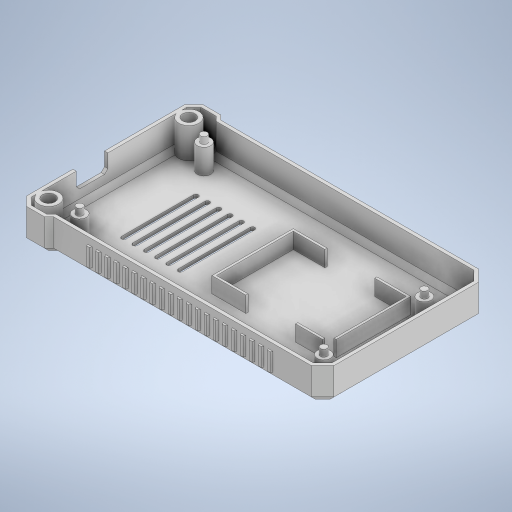
# Autodesk Inventor part: Coque V2
Saved by Autodesk Inventor 2024 (Build 280153000, 153)
## iProperties
Created: 2026-10-31
Part Number: Coque V2
Material: Générique
Document SubType Name: Modeling
Designer: berno
Density: 1 g/cm^3
Appearance: Par défaut
Author: berno
Autodesk Inventor part; units mm, degrees
sketch "Esq Coque" plane through (0, 0, 0) normal (0, 1, 0) x (-1, 0, 0)
  line L0 (-63, -32) -> (-63, 32)
  line L1 (-63, 32) -> (-58, 37)
  line L2 (-58, 37) -> (56, 37)
  line L3 (56, 37) -> (58, 39)
  line L4 (58, 39) -> (66, 39)
  line L5 (66, 39) -> (70, 35)
  line L6 (70, 35) -> (70, -35)
  line L7 (70, -35) -> (66, -39)
  line L8 (66, -39) -> (58, -39)
  line L9 (58, -39) -> (56, -37)
  line L10 (56, -37) -> (-58, -37)
  line L11 (-58, -37) -> (-63, -32)
  constraints: 24 end point
extrude "Coque" add sketch "Esq Coque" along normal blind 15
chamfer "Chanfrein dos" distance 3 angle 45 12 edges at (60.5, 0, 34.5) (1, 0, 37) (-57, 0, 38) (-62, 0, 39) (-68, 0, 37) (-70, 0, 0) (-68, 0, -37) (-62, 0, -39) (-57, 0, -38) (1, 0, -37) (60.5, 0, -34.5) (63, 0, 0)
shell "Evidement" thickness 1.5 removed faces 1 at (-18, 15, -12.3333)
ref_plane "Plan de construction1" through (0, 1.5, 0) normal (0, 1, 0) x (-1, 0, 0)
sketch "Esq Logement batterie" plane through (0, 1.5, 0) normal (0, 1, 0) x (-1, 0, 0)
  line L0 (5, -18) -> (4, -18)
  line L1 (4, -18) -> (4, 18)
  line L2 (4, 18) -> (5, 18)
  line L3 (5, 18) -> (5, -18)
  line L4 (4, 17) -> (-10, 17)
  line L5 (-10, 17) -> (-10, 18)
  line L6 (-10, 18) -> (4, 18)
  line L7 (4, 18) -> (4, 17)
  line L8 (4, -18) -> (-10, -18)
  line L9 (-10, -18) -> (-10, -17)
  line L10 (-10, -17) -> (4, -17)
  line L11 (4, -17) -> (4, -18)
  line L12 (-32, 17) -> (-44, 17)
  line L13 (-44, 17) -> (-44, 18)
  line L14 (-44, 18) -> (-32, 18)
  line L15 (-32, 18) -> (-32, 17)
  line L16 (-32, -18) -> (-46, -18)
  line L17 (-46, -18) -> (-46, -17)
  line L18 (-46, -17) -> (-32, -17)
  line L19 (-32, -17) -> (-32, -18)
  line L20 (-46, -18) -> (-47, -18)
  line L21 (-47, -18) -> (-47, 15)
  line L22 (-47, 15) -> (-46, 15)
  line L23 (-46, 15) -> (-46, -18)
  constraints: 48 end point, 12 parallel, 6 horizontal, 6 perpendicular
extrude "Logement batterie" add sketch "Esq Logement batterie" along normal blind 7
ref_plane "Plan de construction2" through (0, 1.5, 0) normal (0, 1, 0) x (-1, 0, 0)
sketch "Esq Plots carte" plane through (0, 1.5, 0) normal (0, 1, 0) x (-1, 0, 0)
  circle A0 centre (-54, -17) radius 3
  circle A1 centre (54, -27.5) radius 3
  circle A2 centre (54, 27.5) radius 3
  circle A3 centre (-54, 27.5) radius 3
  constraints: 4 centre point
extrude "Plots carte" add sketch "Esq Plots carte" along normal blind 11
ref_plane "Plan de construction3" through (0, 12.5, 0) normal (0, 1, 0) x (-1, 0, 0)
sketch "Esq Pions carte" plane through (0, 12.5, 0) normal (0, 1, 0) x (-1, 0, 0)
  circle A0 centre (-54, -17) radius 1.5
  circle A1 centre (54, -27.5) radius 1.5
  circle A2 centre (54, 27.5) radius 1.5
  circle A3 centre (-54, 27.5) radius 1.5
  constraints: 4 centre point
extrude "Pions carte" add sketch "Esq Pions carte" along normal blind 3
ref_plane "Plan de construction4" through (0, 1.5, 0) normal (0, 1, 0) x (-1, 0, 0)
sketch "Esq Plots inserts" plane through (0, 1.5, 0) normal (0, 1, 0) x (-1, 0, 0)
  circle A0 centre (64.2, 31) radius 4.5
  circle A1 centre (64.2, -31) radius 4.5
  constraints: 2 centre point
extrude "Plots inserts" add sketch "Esq Plots inserts" along normal blind 13.5
ref_plane "Plan de construction5" through (0, 15, 0) normal (0, 1, 0) x (-1, 0, 0)
sketch "Esq Trous inserts M4" plane through (0, 15, 0) normal (0, 1, 0) x (-1, 0, 0)
  circle A0 centre (64.2, 31) radius 2.8
  circle A1 centre (64.2, -31) radius 2.8
  constraints: 2 centre point
extrude "Trous inserts M4" cut sketch "Esq Trous inserts M4" against normal blind 8.5
ref_plane "Plan de construction6" through (-70, 0, 0) normal (1, 0, 0) x (0, 1, 0)
ref_plane "Plan de construction7" through (0, 0, 14.5) normal (0, 0, 1) x (1, 0, 0)
sketch "Esq Fente patte Z+" plane through (0, 0, 14.5) normal (0, 0, 1) x (1, 0, 0)
  line L0 (61, 12.2) -> (62.5, 12.2)
  line L1 (62.5, 12.2) -> (62.5, 13.7)
  line L2 (62.5, 13.7) -> (61.9, 13.7)
  line L3 (61.9, 13.7) -> (61.5, 14.1)
  line L4 (61.5, 14.1) -> (61, 14.1)
  line L5 (61, 14.1) -> (61, 12.2)
  constraints: 12 end point
extrude "Fente patte Z+" cut sketch "Esq Fente patte Z+" along normal mid plane 17
ref_plane "Plan de construction8" through (0, 0, -14.5) normal (0, 0, 1) x (1, 0, 0)
sketch "Esq Fente patte Z-" plane through (0, 0, -14.5) normal (0, 0, 1) x (1, 0, 0)
  line L0 (61, 12.2) -> (62.5, 12.2)
  line L1 (62.5, 12.2) -> (62.5, 13.7)
  line L2 (62.5, 13.7) -> (61.9, 13.7)
  line L3 (61.9, 13.7) -> (61.5, 14.1)
  line L4 (61.5, 14.1) -> (61, 14.1)
  line L5 (61, 14.1) -> (61, 12.2)
  constraints: 12 end point
extrude "Fente patte Z-" cut sketch "Esq Fente patte Z-" along normal mid plane 17
sketch "Esq Ventilation" plane through (0, 0, 0) normal (0, 1, 0) x (-1, 0, 0)
  line L0 (45, -16) -> (45, 16)
  line L1 (47, 16) -> (47, -16)
  arc A0 (47, 16) -> (45, 16) centre (46, 16) ccw
  arc A1 (45, -16) -> (47, -16) centre (46, -16) ccw
  line L2 (40, -16) -> (40, 16)
  line L3 (42, 16) -> (42, -16)
  arc A2 (42, 16) -> (40, 16) centre (41, 16) ccw
  arc A3 (40, -16) -> (42, -16) centre (41, -16) ccw
  line L4 (35, -16) -> (35, 16)
  line L5 (37, 16) -> (37, -16)
  arc A4 (37, 16) -> (35, 16) centre (36, 16) ccw
  arc A5 (35, -16) -> (37, -16) centre (36, -16) ccw
  line L6 (30, -16) -> (30, 16)
  line L7 (32, 16) -> (32, -16)
  arc A6 (32, 16) -> (30, 16) centre (31, 16) ccw
  arc A7 (30, -16) -> (32, -16) centre (31, -16) ccw
  line L8 (25, -16) -> (25, 16)
  line L9 (27, 16) -> (27, -16)
  arc A8 (27, 16) -> (25, 16) centre (26, 16) ccw
  arc A9 (25, -16) -> (27, -16) centre (26, -16) ccw
  line L10 (20, -16) -> (20, 16)
  line L11 (22, 16) -> (22, -16)
  arc A10 (22, 16) -> (20, 16) centre (21, 16) ccw
  arc A11 (20, -16) -> (22, -16) centre (21, -16) ccw
  constraints: 24 end point, 24 point on circle, 12 centre point
extrude "Ventilation" cut sketch "Esq Ventilation" along normal blind 2.5
ref_plane "Plan de construction9" through (-70, 0, 0) normal (1, 0, 0) x (0, 1, 0)
sketch "Esq Ouverture USB-C" plane through (-70, 0, 0) normal (1, 0, 0) x (0, 1, 0)
  line L0 (15.5, 0.5) -> (9, 0.5)
  line L1 (9, 0.5) -> (7.5, 2)
  line L2 (7.5, 2) -> (7.5, 13)
  line L3 (7.5, 13) -> (9, 14.5)
  line L4 (9, 14.5) -> (15.5, 14.5)
  line L5 (15.5, 14.5) -> (15.5, 0.5)
  constraints: 12 end point
extrude "Ouverture USB-C" cut sketch "Esq Ouverture USB-C" along normal mid plane 5
ref_plane "Plan de construction10" through (0, 4, 0) normal (0, 1, 0) x (-1, 0, 0)
ref_plane "Plan de construction11" through (0, 4, 0) normal (0, 1, 0) x (-1, 0, 0)
sketch "Esq Nervures cotes" plane through (0, 4, 0) normal (0, 1, 0) x (-1, 0, 0)
  line L0 (41, 36.8) -> (39, 36.8)
  line L1 (39, 36.8) -> (39, 37)
  line L2 (39, 37) -> (39.4, 37.8)
  line L3 (39.4, 37.8) -> (40.6, 37.8)
  line L4 (40.6, 37.8) -> (41, 37)
  line L5 (41, 37) -> (41, 36.8)
  line L6 (41, -36.8) -> (39, -36.8)
  line L7 (39, -36.8) -> (39, -37)
  line L8 (39, -37) -> (39.4, -37.8)
  line L9 (39.4, -37.8) -> (40.6, -37.8)
  line L10 (40.6, -37.8) -> (41, -37)
  line L11 (41, -37) -> (41, -36.8)
  line L12 (37, 36.8) -> (35, 36.8)
  line L13 (35, 36.8) -> (35, 37)
  line L14 (35, 37) -> (35.4, 37.8)
  line L15 (35.4, 37.8) -> (36.6, 37.8)
  line L16 (36.6, 37.8) -> (37, 37)
  line L17 (37, 37) -> (37, 36.8)
  line L18 (37, -36.8) -> (35, -36.8)
  line L19 (35, -36.8) -> (35, -37)
  line L20 (35, -37) -> (35.4, -37.8)
  line L21 (35.4, -37.8) -> (36.6, -37.8)
  line L22 (36.6, -37.8) -> (37, -37)
  line L23 (37, -37) -> (37, -36.8)
  line L24 (33, 36.8) -> (31, 36.8)
  line L25 (31, 36.8) -> (31, 37)
  line L26 (31, 37) -> (31.4, 37.8)
  line L27 (31.4, 37.8) -> (32.6, 37.8)
  line L28 (32.6, 37.8) -> (33, 37)
  line L29 (33, 37) -> (33, 36.8)
  line L30 (33, -36.8) -> (31, -36.8)
  line L31 (31, -36.8) -> (31, -37)
  line L32 (31, -37) -> (31.4, -37.8)
  line L33 (31.4, -37.8) -> (32.6, -37.8)
  line L34 (32.6, -37.8) -> (33, -37)
  line L35 (33, -37) -> (33, -36.8)
  line L36 (29, 36.8) -> (27, 36.8)
  line L37 (27, 36.8) -> (27, 37)
  line L38 (27, 37) -> (27.4, 37.8)
  line L39 (27.4, 37.8) -> (28.6, 37.8)
  line L40 (28.6, 37.8) -> (29, 37)
  line L41 (29, 37) -> (29, 36.8)
  line L42 (29, -36.8) -> (27, -36.8)
  line L43 (27, -36.8) -> (27, -37)
  line L44 (27, -37) -> (27.4, -37.8)
  line L45 (27.4, -37.8) -> (28.6, -37.8)
  line L46 (28.6, -37.8) -> (29, -37)
  line L47 (29, -37) -> (29, -36.8)
  line L48 (25, 36.8) -> (23, 36.8)
  line L49 (23, 36.8) -> (23, 37)
  line L50 (23, 37) -> (23.4, 37.8)
  line L51 (23.4, 37.8) -> (24.6, 37.8)
  line L52 (24.6, 37.8) -> (25, 37)
  line L53 (25, 37) -> (25, 36.8)
  line L54 (25, -36.8) -> (23, -36.8)
  line L55 (23, -36.8) -> (23, -37)
  line L56 (23, -37) -> (23.4, -37.8)
  line L57 (23.4, -37.8) -> (24.6, -37.8)
  line L58 (24.6, -37.8) -> (25, -37)
  line L59 (25, -37) -> (25, -36.8)
  line L60 (21, 36.8) -> (19, 36.8)
  line L61 (19, 36.8) -> (19, 37)
  line L62 (19, 37) -> (19.4, 37.8)
  line L63 (19.4, 37.8) -> (20.6, 37.8)
  line L64 (20.6, 37.8) -> (21, 37)
  line L65 (21, 37) -> (21, 36.8)
  line L66 (21, -36.8) -> (19, -36.8)
  line L67 (19, -36.8) -> (19, -37)
  line L68 (19, -37) -> (19.4, -37.8)
  line L69 (19.4, -37.8) -> (20.6, -37.8)
  line L70 (20.6, -37.8) -> (21, -37)
  line L71 (21, -37) -> (21, -36.8)
  line L72 (17, 36.8) -> (15, 36.8)
  line L73 (15, 36.8) -> (15, 37)
  line L74 (15, 37) -> (15.4, 37.8)
  line L75 (15.4, 37.8) -> (16.6, 37.8)
  line L76 (16.6, 37.8) -> (17, 37)
  line L77 (17, 37) -> (17, 36.8)
  line L78 (17, -36.8) -> (15, -36.8)
  line L79 (15, -36.8) -> (15, -37)
  line L80 (15, -37) -> (15.4, -37.8)
  line L81 (15.4, -37.8) -> (16.6, -37.8)
  line L82 (16.6, -37.8) -> (17, -37)
  line L83 (17, -37) -> (17, -36.8)
  line L84 (13, 36.8) -> (11, 36.8)
  line L85 (11, 36.8) -> (11, 37)
  line L86 (11, 37) -> (11.4, 37.8)
  line L87 (11.4, 37.8) -> (12.6, 37.8)
  line L88 (12.6, 37.8) -> (13, 37)
  line L89 (13, 37) -> (13, 36.8)
  line L90 (13, -36.8) -> (11, -36.8)
  line L91 (11, -36.8) -> (11, -37)
  line L92 (11, -37) -> (11.4, -37.8)
  line L93 (11.4, -37.8) -> (12.6, -37.8)
  line L94 (12.6, -37.8) -> (13, -37)
  line L95 (13, -37) -> (13, -36.8)
  line L96 (9, 36.8) -> (7, 36.8)
  line L97 (7, 36.8) -> (7, 37)
  line L98 (7, 37) -> (7.4, 37.8)
  line L99 (7.4, 37.8) -> (8.6, 37.8)
  line L100 (8.6, 37.8) -> (9, 37)
  line L101 (9, 37) -> (9, 36.8)
  line L102 (9, -36.8) -> (7, -36.8)
  line L103 (7, -36.8) -> (7, -37)
  line L104 (7, -37) -> (7.4, -37.8)
  line L105 (7.4, -37.8) -> (8.6, -37.8)
  line L106 (8.6, -37.8) -> (9, -37)
  line L107 (9, -37) -> (9, -36.8)
  line L108 (5, 36.8) -> (3, 36.8)
  line L109 (3, 36.8) -> (3, 37)
  line L110 (3, 37) -> (3.4, 37.8)
  line L111 (3.4, 37.8) -> (4.6, 37.8)
  line L112 (4.6, 37.8) -> (5, 37)
  line L113 (5, 37) -> (5, 36.8)
  line L114 (5, -36.8) -> (3, -36.8)
  line L115 (3, -36.8) -> (3, -37)
  line L116 (3, -37) -> (3.4, -37.8)
  line L117 (3.4, -37.8) -> (4.6, -37.8)
  line L118 (4.6, -37.8) -> (5, -37)
  line L119 (5, -37) -> (5, -36.8)
  line L120 (1, 36.8) -> (-1, 36.8)
  line L121 (-1, 36.8) -> (-1, 37)
  line L122 (-1, 37) -> (-0.6, 37.8)
  line L123 (-0.6, 37.8) -> (0.6, 37.8)
  line L124 (0.6, 37.8) -> (1, 37)
  line L125 (1, 37) -> (1, 36.8)
  line L126 (1, -36.8) -> (-1, -36.8)
  line L127 (-1, -36.8) -> (-1, -37)
  line L128 (-1, -37) -> (-0.6, -37.8)
  line L129 (-0.6, -37.8) -> (0.6, -37.8)
  line L130 (0.6, -37.8) -> (1, -37)
  line L131 (1, -37) -> (1, -36.8)
  line L132 (-3, 36.8) -> (-5, 36.8)
  line L133 (-5, 36.8) -> (-5, 37)
  line L134 (-5, 37) -> (-4.6, 37.8)
  line L135 (-4.6, 37.8) -> (-3.4, 37.8)
  line L136 (-3.4, 37.8) -> (-3, 37)
  line L137 (-3, 37) -> (-3, 36.8)
  line L138 (-3, -36.8) -> (-5, -36.8)
  line L139 (-5, -36.8) -> (-5, -37)
  line L140 (-5, -37) -> (-4.6, -37.8)
  line L141 (-4.6, -37.8) -> (-3.4, -37.8)
  line L142 (-3.4, -37.8) -> (-3, -37)
  line L143 (-3, -37) -> (-3, -36.8)
  line L144 (-7, 36.8) -> (-9, 36.8)
  line L145 (-9, 36.8) -> (-9, 37)
  line L146 (-9, 37) -> (-8.6, 37.8)
  line L147 (-8.6, 37.8) -> (-7.4, 37.8)
  line L148 (-7.4, 37.8) -> (-7, 37)
  line L149 (-7, 37) -> (-7, 36.8)
  line L150 (-7, -36.8) -> (-9, -36.8)
  line L151 (-9, -36.8) -> (-9, -37)
  line L152 (-9, -37) -> (-8.6, -37.8)
  line L153 (-8.6, -37.8) -> (-7.4, -37.8)
  line L154 (-7.4, -37.8) -> (-7, -37)
  line L155 (-7, -37) -> (-7, -36.8)
  line L156 (-11, 36.8) -> (-13, 36.8)
  line L157 (-13, 36.8) -> (-13, 37)
  line L158 (-13, 37) -> (-12.6, 37.8)
  line L159 (-12.6, 37.8) -> (-11.4, 37.8)
  line L160 (-11.4, 37.8) -> (-11, 37)
  line L161 (-11, 37) -> (-11, 36.8)
  line L162 (-11, -36.8) -> (-13, -36.8)
  line L163 (-13, -36.8) -> (-13, -37)
  line L164 (-13, -37) -> (-12.6, -37.8)
  line L165 (-12.6, -37.8) -> (-11.4, -37.8)
  line L166 (-11.4, -37.8) -> (-11, -37)
  line L167 (-11, -37) -> (-11, -36.8)
  line L168 (-15, 36.8) -> (-17, 36.8)
  line L169 (-17, 36.8) -> (-17, 37)
  line L170 (-17, 37) -> (-16.6, 37.8)
  line L171 (-16.6, 37.8) -> (-15.4, 37.8)
  line L172 (-15.4, 37.8) -> (-15, 37)
  line L173 (-15, 37) -> (-15, 36.8)
  line L174 (-15, -36.8) -> (-17, -36.8)
  line L175 (-17, -36.8) -> (-17, -37)
  line L176 (-17, -37) -> (-16.6, -37.8)
  line L177 (-16.6, -37.8) -> (-15.4, -37.8)
  line L178 (-15.4, -37.8) -> (-15, -37)
  line L179 (-15, -37) -> (-15, -36.8)
  line L180 (-19, 36.8) -> (-21, 36.8)
  line L181 (-21, 36.8) -> (-21, 37)
  line L182 (-21, 37) -> (-20.6, 37.8)
  line L183 (-20.6, 37.8) -> (-19.4, 37.8)
  line L184 (-19.4, 37.8) -> (-19, 37)
  line L185 (-19, 37) -> (-19, 36.8)
  line L186 (-19, -36.8) -> (-21, -36.8)
  line L187 (-21, -36.8) -> (-21, -37)
  line L188 (-21, -37) -> (-20.6, -37.8)
  line L189 (-20.6, -37.8) -> (-19.4, -37.8)
  line L190 (-19.4, -37.8) -> (-19, -37)
  line L191 (-19, -37) -> (-19, -36.8)
  line L192 (-23, 36.8) -> (-25, 36.8)
  line L193 (-25, 36.8) -> (-25, 37)
  line L194 (-25, 37) -> (-24.6, 37.8)
  line L195 (-24.6, 37.8) -> (-23.4, 37.8)
  line L196 (-23.4, 37.8) -> (-23, 37)
  line L197 (-23, 37) -> (-23, 36.8)
  line L198 (-23, -36.8) -> (-25, -36.8)
  line L199 (-25, -36.8) -> (-25, -37)
  line L200 (-25, -37) -> (-24.6, -37.8)
  line L201 (-24.6, -37.8) -> (-23.4, -37.8)
  line L202 (-23.4, -37.8) -> (-23, -37)
  line L203 (-23, -37) -> (-23, -36.8)
  line L204 (-27, 36.8) -> (-29, 36.8)
  line L205 (-29, 36.8) -> (-29, 37)
  line L206 (-29, 37) -> (-28.6, 37.8)
  line L207 (-28.6, 37.8) -> (-27.4, 37.8)
  line L208 (-27.4, 37.8) -> (-27, 37)
  line L209 (-27, 37) -> (-27, 36.8)
  line L210 (-27, -36.8) -> (-29, -36.8)
  line L211 (-29, -36.8) -> (-29, -37)
  line L212 (-29, -37) -> (-28.6, -37.8)
  line L213 (-28.6, -37.8) -> (-27.4, -37.8)
  line L214 (-27.4, -37.8) -> (-27, -37)
  line L215 (-27, -37) -> (-27, -36.8)
  line L216 (-31, 36.8) -> (-33, 36.8)
  line L217 (-33, 36.8) -> (-33, 37)
  line L218 (-33, 37) -> (-32.6, 37.8)
  line L219 (-32.6, 37.8) -> (-31.4, 37.8)
  line L220 (-31.4, 37.8) -> (-31, 37)
  line L221 (-31, 37) -> (-31, 36.8)
  line L222 (-31, -36.8) -> (-33, -36.8)
  line L223 (-33, -36.8) -> (-33, -37)
  line L224 (-33, -37) -> (-32.6, -37.8)
  line L225 (-32.6, -37.8) -> (-31.4, -37.8)
  line L226 (-31.4, -37.8) -> (-31, -37)
  line L227 (-31, -37) -> (-31, -36.8)
  line L228 (-35, 36.8) -> (-37, 36.8)
  line L229 (-37, 36.8) -> (-37, 37)
  line L230 (-37, 37) -> (-36.6, 37.8)
  line L231 (-36.6, 37.8) -> (-35.4, 37.8)
  line L232 (-35.4, 37.8) -> (-35, 37)
  line L233 (-35, 37) -> (-35, 36.8)
  line L234 (-35, -36.8) -> (-37, -36.8)
  line L235 (-37, -36.8) -> (-37, -37)
  line L236 (-37, -37) -> (-36.6, -37.8)
  line L237 (-36.6, -37.8) -> (-35.4, -37.8)
  line L238 (-35.4, -37.8) -> (-35, -37)
  line L239 (-35, -37) -> (-35, -36.8)
  line L240 (-39, 36.8) -> (-41, 36.8)
  line L241 (-41, 36.8) -> (-41, 37)
  line L242 (-41, 37) -> (-40.6, 37.8)
  line L243 (-40.6, 37.8) -> (-39.4, 37.8)
  line L244 (-39.4, 37.8) -> (-39, 37)
  line L245 (-39, 37) -> (-39, 36.8)
  line L246 (-39, -36.8) -> (-41, -36.8)
  line L247 (-41, -36.8) -> (-41, -37)
  line L248 (-41, -37) -> (-40.6, -37.8)
  line L249 (-40.6, -37.8) -> (-39.4, -37.8)
  line L250 (-39.4, -37.8) -> (-39, -37)
  line L251 (-39, -37) -> (-39, -36.8)
  constraints: 504 end point
extrude "Nervures cotes" add sketch "Esq Nervures cotes" along normal blind 8
